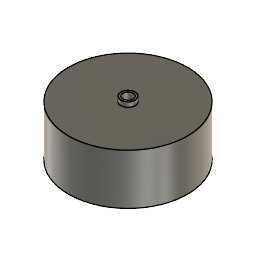
Yellow Motor Wheel (Autodesk Fusion 360 design; units mm, degrees)
Autodesk Fusion 360 part; units mm, degrees
sketch "Sketch4" plane through (0, 0, 0) normal (0, 0, 1) x (1, 0, 0)
  circle A0 centre (0, 0) radius 31.75
  dimension "d14" = 63.5
  constraint coincident A0.centre origin
  measures "d14" diameter of A0
extrude "Extrude4" add sketch "Sketch4" along normal blind 26.924
sketch "Sketch5" plane through (0, 0, 26.924) normal (0, 0, 1) x (-1, 0, 0)
  circle A0 centre (0, 0) radius 31.75
  circle A1 centre (0, 0) radius 2.7
  circle A2 centre (0, 0) radius 3.81
  dimension "d17" = 5.4
  dimension "d18" = 7.62
  constraint concentric A0 A1
  constraint concentric A1 A2
  measures "d17" diameter of A1
  measures "d18" diameter of A2
extrude "Extrude5" add sketch "Sketch5" along normal blind 2.54 contours A2
extrude "Extrude6" cut 1 faces at (-0.0791, 0.5246, 26.924) along direction (0, 0, -1) blind 5.36
equation "d21 = -0.0079 m + 0.1 in"
